Autodesk Fusion 360 part; units mm, degrees
(part 3 of 4)
sketch "SRD relay envelope 1 sketch" plane through (0, 0, 9.6) normal (0, 0, 1) x (1, 0, 0) in component "REF relay envelope 75.5x55x20 - variant not confirmed"
  line L0 (36.75, 131) -> (52.25, 131)
  line L1 (52.25, 131) -> (52.25, 150)
  line L2 (52.25, 150) -> (36.75, 150)
  line L3 (36.75, 150) -> (36.75, 131)
extrude "SRD relay envelope 1" add sketch "SRD relay envelope 1 sketch" along normal blind 15.5 separate body makes body 31 in component "REF relay envelope 75.5x55x20 - variant not confirmed"
ref_plane "WorkPlane3" through (0, 0, 9.6) normal (0, 0, 1) x (1, 0, 0) in component "REF relay envelope 75.5x55x20 - variant not confirmed"
sketch "SRD relay envelope 2 sketch" plane through (0, 0, 9.6) normal (0, 0, 1) x (1, 0, 0) in component "REF relay envelope 75.5x55x20 - variant not confirmed"
  line L0 (54.05, 131) -> (69.55, 131)
  line L1 (69.55, 131) -> (69.55, 150)
  line L2 (69.55, 150) -> (54.05, 150)
  line L3 (54.05, 150) -> (54.05, 131)
extrude "SRD relay envelope 2" add sketch "SRD relay envelope 2 sketch" along normal blind 15.5 separate body makes body 32 in component "REF relay envelope 75.5x55x20 - variant not confirmed"
ref_plane "WorkPlane4" through (0, 0, 9.6) normal (0, 0, 1) x (1, 0, 0) in component "REF relay envelope 75.5x55x20 - variant not confirmed"
sketch "SRD relay envelope 3 sketch" plane through (0, 0, 9.6) normal (0, 0, 1) x (1, 0, 0) in component "REF relay envelope 75.5x55x20 - variant not confirmed"
  line L0 (71.35, 131) -> (86.85, 131)
  line L1 (86.85, 131) -> (86.85, 150)
  line L2 (86.85, 150) -> (71.35, 150)
  line L3 (71.35, 150) -> (71.35, 131)
extrude "SRD relay envelope 3" add sketch "SRD relay envelope 3 sketch" along normal blind 15.5 separate body makes body 33 in component "REF relay envelope 75.5x55x20 - variant not confirmed"
ref_plane "WorkPlane5" through (0, 0, 9.6) normal (0, 0, 1) x (1, 0, 0) in component "REF relay envelope 75.5x55x20 - variant not confirmed"
sketch "SRD relay envelope 4 sketch" plane through (0, 0, 9.6) normal (0, 0, 1) x (1, 0, 0) in component "REF relay envelope 75.5x55x20 - variant not confirmed"
  line L0 (88.65, 131) -> (104.15, 131)
  line L1 (104.15, 131) -> (104.15, 150)
  line L2 (104.15, 150) -> (88.65, 150)
  line L3 (88.65, 150) -> (88.65, 131)
extrude "SRD relay envelope 4" add sketch "SRD relay envelope 4 sketch" along normal blind 15.5 separate body makes body 34 in component "REF relay envelope 75.5x55x20 - variant not confirmed"
ref_plane "WorkPlane6" through (0, 0, 9.6) normal (0, 0, 1) x (1, 0, 0) in component "REF relay envelope 75.5x55x20 - variant not confirmed"
sketch "Terminal strip envelope sketch" plane through (0, 0, 9.6) normal (0, 0, 1) x (1, 0, 0) in component "REF relay envelope 75.5x55x20 - variant not confirmed"
  line L0 (37, 155) -> (103, 155)
  line L1 (103, 155) -> (103, 165)
  line L2 (103, 165) -> (37, 165)
  line L3 (37, 165) -> (37, 155)
extrude "Terminal strip envelope" add sketch "Terminal strip envelope sketch" along normal blind 12 separate body makes body 35 in component "REF relay envelope 75.5x55x20 - variant not confirmed"
ref_plane "WorkPlane7" through (0, 0, 9.6) normal (0, 0, 1) x (1, 0, 0) in component "REF relay envelope 75.5x55x20 - variant not confirmed"
sketch "Control connector reserve sketch" plane through (0, 0, 9.6) normal (0, 0, 1) x (1, 0, 0) in component "REF relay envelope 75.5x55x20 - variant not confirmed"
  line L0 (41, 114) -> (77, 114)
  line L1 (77, 114) -> (77, 119)
  line L2 (77, 119) -> (41, 119)
  line L3 (41, 119) -> (41, 114)
extrude "Control connector reserve" add sketch "Control connector reserve sketch" along normal blind 18.4 separate body makes body 36 in component "REF relay envelope 75.5x55x20 - variant not confirmed"
ref_plane "WorkPlane1" through (0, 0, 49.6) normal (0, 0, 1) x (1, 0, 0) in component "REF LCD2004 98x60 - 93x55 mounting - conservative thickness"
sketch "LCD PCB 98x60 sketch" plane through (0, 0, 49.6) normal (0, 0, 1) x (1, 0, 0) in component "REF LCD2004 98x60 - 93x55 mounting - conservative thickness"
  line L0 (21, 98) -> (119, 98)
  line L1 (119, 98) -> (119, 158)
  line L2 (119, 158) -> (21, 158)
  line L3 (21, 158) -> (21, 98)
extrude "LCD PCB 98x60" add sketch "LCD PCB 98x60 sketch" along normal blind 1.6 separate body makes body 37 in component "REF LCD2004 98x60 - 93x55 mounting - conservative thickness"
ref_plane "WorkPlane2" through (0, 0, 49.5) normal (0, 0, 1) x (1, 0, 0) in component "REF LCD2004 98x60 - 93x55 mounting - conservative thickness"
sketch "LCD minimum published hole diameter sketch" plane through (0, 0, 49.5) normal (0, 0, 1) x (1, 0, 0) in component "REF LCD2004 98x60 - 93x55 mounting - conservative thickness"
  circle A0 centre (23.5, 100.5) radius 1.25
  circle A1 centre (116.5, 100.5) radius 1.25
  circle A2 centre (23.5, 155.5) radius 1.25
  circle A3 centre (116.5, 155.5) radius 1.25
extrude "LCD minimum published hole diameter" cut sketch "LCD minimum published hole diameter sketch" along normal blind 1.8 bodies 37 in component "REF LCD2004 98x60 - 93x55 mounting - conservative thickness"
ref_plane "WorkPlane3" through (0, 0, 51.2) normal (0, 0, 1) x (1, 0, 0) in component "REF LCD2004 98x60 - 93x55 mounting - conservative thickness"
sketch "LCD bezel depth envelope sketch" plane through (0, 0, 51.2) normal (0, 0, 1) x (1, 0, 0) in component "REF LCD2004 98x60 - 93x55 mounting - conservative thickness"
  line L0 (21.5, 108.8) -> (118.5, 108.8)
  line L1 (118.5, 108.8) -> (118.5, 147.2)
  line L2 (118.5, 147.2) -> (21.5, 147.2)
  line L3 (21.5, 147.2) -> (21.5, 108.8)
extrude "LCD bezel depth envelope" add sketch "LCD bezel depth envelope sketch" along normal blind 12 separate body makes body 38 in component "REF LCD2004 98x60 - 93x55 mounting - conservative thickness"
ref_plane "WorkPlane4" through (0, 0, 63.2) normal (0, 0, 1) x (1, 0, 0) in component "REF LCD2004 98x60 - 93x55 mounting - conservative thickness"
sketch "LCD viewing area envelope sketch" plane through (0, 0, 63.2) normal (0, 0, 1) x (1, 0, 0) in component "REF LCD2004 98x60 - 93x55 mounting - conservative thickness"
  line L0 (31.5, 115.4) -> (108.5, 115.4)
  line L1 (108.5, 115.4) -> (108.5, 140.6)
  line L2 (108.5, 140.6) -> (31.5, 140.6)
  line L3 (31.5, 140.6) -> (31.5, 115.4)
extrude "LCD viewing area envelope" add sketch "LCD viewing area envelope sketch" along normal blind 0.1 separate body makes body 39 in component "REF LCD2004 98x60 - 93x55 mounting - conservative thickness"
ref_plane "WorkPlane5" through (0, 0, 39.2) normal (0, 0, 1) x (1, 0, 0) in component "REF LCD2004 98x60 - 93x55 mounting - conservative thickness"
sketch "LCD I2C backpack reserve sketch" plane through (0, 0, 39.2) normal (0, 0, 1) x (1, 0, 0) in component "REF LCD2004 98x60 - 93x55 mounting - conservative thickness"
  line L0 (32, 100) -> (74, 100)
  line L1 (74, 100) -> (74, 118)
  line L2 (74, 118) -> (32, 118)
  line L3 (32, 118) -> (32, 100)
extrude "LCD I2C backpack reserve" add sketch "LCD I2C backpack reserve sketch" along normal blind 10.4 separate body makes body 40 in component "REF LCD2004 98x60 - 93x55 mounting - conservative thickness"
sketch "Sketch1" plane through (0, 0, 0) normal (0, -1, 0) x (1, 0, 0)
  line L0 (6, 0) -> (134, 0)
  line L1 (134, 0) -> (134, 64)
  line L2 (134, 64) -> (6, 64)
  line L3 (6, 64) -> (6, 0)
  line L4 (6, 64) -> (134, 64)
  line L5 (134, 64) -> (134, 0)
  line L6 (134, 0) -> (6, 0)
  line L7 (6, 0) -> (6, 64)
  line L8 (50, 52) -> (90, 52)
  line L9 (90, 52) -> (90, 12)
  line L10 (90, 12) -> (50, 12)
  line L11 (50, 12) -> (50, 52)
  dimension "d962" = 128
  dimension "d963" = 64
  dimension "d964" = 40
  dimension "d965" = 40
  dimension "d966" = 44
  dimension "d967" = 12
  constraint horizontal L4
  constraint vertical L5
  constraint horizontal L6
  constraint vertical L7
  constraint coincident L0.end L1.start
  constraint coincident L2.end L3.start
  constraint horizontal L8
  constraint vertical L9
  constraint horizontal L10
  constraint vertical L11
  measures "d962" distance of L2.end L1.end
  measures "d963" distance of L2.end L0.start
  measures "d964" distance of L8.start L8.end
  measures "d965" distance of L8.start L10.end
  measures "d966" distance of L7 L11
  measures "d967" distance of L4 L8
extrude "Extrude41" cut sketch "Sketch1" against normal blind 3 contours L8 L9 L10 L11 bodies 1 in component "01 BASE - PCB at bottom"
split "Split1" by plane through (70, 45, 32) normal (0, 1, 0) bodies 1 makes body 41 at (46.6667, 131, 0) in component "01 BASE - PCB at bottom"
sketch "Sketch2" plane through (0, 3, 0) normal (0, 1, 0) x (-1, 0, 0)
  line L0 (-90, 12) -> (-90, 52)
  line L1 (-90, 52) -> (-50, 52)
  line L2 (-50, 52) -> (-50, 12)
  line L3 (-50, 12) -> (-90, 12)
  line L4 (-13, 3) -> (-13, 64)
  line L5 (-13, 64) -> (-127, 64)
  line L6 (-127, 64) -> (-127, 3)
  line L7 (-127, 3) -> (-13, 3)
  line L8 (-90, 52) -> (-85, 52)
  line L9 (-85, 52) -> (-85, 48)
  line L10 (-86, 47) -> (-90, 47)
  line L11 (-90, 47) -> (-90, 52)
  line L12 (-50, 52) -> (-55, 52)
  line L13 (-55, 52) -> (-55, 48)
  line L14 (-54, 47) -> (-50, 47)
  line L15 (-50, 47) -> (-50, 52)
  line L16 (-50, 12) -> (-55, 12)
  line L17 (-55, 12) -> (-55, 16)
  line L18 (-54, 17) -> (-50, 17)
  line L19 (-50, 17) -> (-50, 12)
  line L20 (-90, 12) -> (-85, 12)
  line L21 (-85, 12) -> (-85, 16)
  line L22 (-86, 17) -> (-90, 17)
  line L23 (-90, 17) -> (-90, 12)
  line L24 (-86, 47) -> (-95, 47)
  line L25 (-95, 47) -> (-95, 57)
  line L26 (-95, 57) -> (-85, 57)
  line L27 (-85, 57) -> (-85, 48)
  line L28 (-86, 17) -> (-95, 17)
  line L29 (-95, 17) -> (-95, 7)
  line L30 (-95, 7) -> (-85, 7)
  line L31 (-85, 7) -> (-85, 16)
  line L32 (-54, 17) -> (-45, 17)
  line L33 (-45, 17) -> (-45, 7)
  line L34 (-45, 7) -> (-55, 7)
  line L35 (-55, 7) -> (-55, 16)
  line L36 (-54, 47) -> (-45, 47)
  line L37 (-45, 47) -> (-45, 57)
  line L38 (-45, 57) -> (-55, 57)
  line L39 (-55, 57) -> (-55, 48)
  arc A0 (-85, 16) -> (-86, 17) centre (-86, 16) ccw
  arc A1 (-54, 17) -> (-55, 16) centre (-54, 16) ccw
  arc A2 (-55, 48) -> (-54, 47) centre (-54, 48) ccw
  arc A3 (-86, 47) -> (-85, 48) centre (-86, 48) ccw
  circle A4 centre (-87.6464, 49.6464) radius 1
  circle A5 centre (-52.3536, 49.6464) radius 1
  circle A6 centre (-52.3536, 14.3536) radius 1
  circle A7 centre (-87.6464, 14.3536) radius 1
  line L40 (-50, 52) -> (-45, 52)
  line L41 (-90, 52) -> (-95, 52)
  dimension "d972" = 1
  dimension "d973" = 1
  dimension "d974" = 1
  dimension "d975" = 1
  dimension "d976" = 2
  dimension "d977" = 2
  dimension "d978" = 2
  dimension "d979" = 2
  constraint horizontal L8
  constraint vertical L9
  constraint horizontal L10
  constraint vertical L11
  constraint coincident L0.end L1.start
  constraint horizontal L12
  constraint vertical L13
  constraint horizontal L14
  constraint vertical L15
  constraint coincident L1.end L2.start
  constraint horizontal L16
  constraint vertical L17
  constraint horizontal L18
  constraint vertical L19
  constraint coincident L2.end L3.start
  constraint horizontal L20
  constraint vertical L21
  constraint horizontal L22
  constraint vertical L23
  constraint coincident L0.start L3.end
  constraint horizontal L24
  constraint vertical L25
  constraint horizontal L26
  constraint vertical L27
  constraint horizontal L28
  constraint vertical L29
  constraint horizontal L30
  constraint vertical L31
  constraint horizontal L32
  constraint vertical L33
  constraint horizontal L34
  constraint vertical L35
  constraint horizontal L36
  constraint vertical L37
  constraint horizontal L38
  constraint vertical L39
  constraint tangent L28 A0
  constraint tangent L21 A0
  constraint tangent L35 A1
  constraint tangent L32 A1
  constraint tangent L13 A2
  constraint tangent L14 A2
  constraint tangent L9 A3
  constraint tangent L24 A3
  constraint midpoint L37 L40.end
  constraint midpoint L25 L41.end
  measures "d972" radius of A0
  measures "d973" radius of A1
  measures "d974" radius of A2
  measures "d975" radius of A3
  measures "d976" diameter of A4
  measures "d977" diameter of A5
  measures "d978" diameter of A6
  measures "d979" diameter of A7
extrude "Extrude42" add sketch "Sketch2" along normal blind -1.5 and the other way blind 3 contours L0 L3 L20 L21 L22 L23 L28 L31 A0 | L0 L1 L8 L9 L10 L11 L24 L27 A3 | L2 L3 L16 L17 L18 L19 L32 L35 A1 | L1 L2 L12 L13 L14 L15 L36 L39 A2 bodies 1 in component "01 BASE - PCB at bottom"
fillet "Fillet1" radius 16 8 edges at (50, 0.75, 47) (50, 0.75, 17) (85, 0.75, 52) (55, 0.75, 52) (90, 0.75, 17) (85, 0.75, 12) (90, 0.75, 47) (55, 0.75, 12) on bodies 1 in component "01 BASE - PCB at bottom"
combine "Combine1" operation add target body 1 tool bodies 41 in component "01 BASE - PCB at bottom"
ref_plane "WorkPlane2" through (10, 90, 32) normal (-1, 0, 0) x (0, -1, 0)
split "Split2" by plane through (10, 90, 32) normal (-1, 0, 0) bodies 1 makes body 42 at (0, 62, 21.3333) in component "01 BASE - PCB at bottom"
sketch "Sketch3" plane through (10, 0, 0) normal (-1, 0, 0) x (0, -1, 0)
  circle A0 centre (-83, 16) radius 5.5
  dimension "d988" = 11
  measures "d988" diameter of A0
extrude "Extrude43" cut sketch "Sketch3" along normal blind 59 draft 5 bodies 42 in component "01 BASE - PCB at bottom"
sketch "Sketch4" plane through (25, 0, 0) normal (1, 0, 0) x (0, 1, 0)
  line L0 (23, 11) -> (39, 11)
  line L1 (39, 11) -> (39, 23)
  line L2 (39, 23) -> (23, 23)
  line L3 (23, 23) -> (23, 11)
  line L4 (23, 23) -> (35, 23)
  line L5 (35, 23) -> (35, 15)
  line L6 (35, 15) -> (23, 15)
  line L7 (23, 15) -> (23, 23)
  dimension "d991" = 12
  dimension "d992" = 8
  constraint horizontal L4
  constraint vertical L5
  constraint horizontal L6
  constraint vertical L7
  constraint coincident L2.end L3.start
  measures "d991" distance of L2.end L4.end
  measures "d992" distance of L2.end L6.end
extrude "Extrude44" cut sketch "Sketch4" along normal blind -25 and the other way blind 20 contours L2 L3 L4 L5 L6 L7 bodies 42 in component "01 BASE - PCB at bottom"
sketch "Sketch5" plane through (0, 0, 0) normal (-1, 0, 0) x (0, -1, 0)
  line L0 (-35, 15) -> (-35, 23)
  line L1 (-35, 23) -> (-23, 23)
  line L2 (-23, 23) -> (-23, 15)
  line L3 (-23, 15) -> (-35, 15)
  circle A0 centre (-83, 16) radius 6.3749
  line L4 (-174, 0) -> (-6, 0)
  line L5 (-6, 0) -> (-6, 64)
  line L6 (-6, 64) -> (-174, 64)
  line L7 (-174, 64) -> (-174, 0)
  circle A1 centre (-41, 19) radius 2
  dimension "d997" = 4
  measures "d997" diameter of A1
extrude "Extrude45" cut sketch "Sketch5" against normal blind 8 contours A1 bodies 42 in component "01 BASE - PCB at bottom"
combine "Combine2" operation add target body 42 tool bodies 1 in component "01 BASE - PCB at bottom"
sketch "Sketch6" plane through (0, 0, 67) normal (0, 0, 1) x (-1, 0, 0)
  spline S0 degree 3 poles (-38.9727, -80.2046) (-38.8334, -80.304) (-38.5543, -80.503) (-38.384, -80.8005) (-38.2988, -80.9495) knots 0 0 0 0 0.050683 0.101518 0.101518 0.101518 0.101518
  spline S1 degree 3 poles (-38.2988, -80.9495) (-38.2319, -81.1092) (-38.0981, -81.4289) (-38.0791, -81.775) (-38.0696, -81.9482) knots 0 0 0 0 0.05152 0.103135 0.103135 0.103135 0.103135
  spline S2 degree 3 poles (-38.0696, -81.9482) (-38.085, -82.2545) (-38.114, -82.8278) (-38.4486, -83.2916) (-38.6044, -83.5075) knots 0 0 0 0 0.08978 0.168002 0.168002 0.168002 0.168002
  spline S3 degree 3 poles (-38.6044, -83.5075) (-38.7988, -83.6718) (-39.1974, -84.0085) (-39.7183, -84.0498) (-39.985, -84.0709) knots 0 0 0 0 0.074417 0.152506 0.152506 0.152506 0.152506
  spline S4 degree 3 poles (-39.985, -84.0709) (-40.1637, -84.0607) (-40.5148, -84.0407) (-40.8292, -83.8835) (-40.9836, -83.8063) knots 0 0 0 0 0.053075 0.104281 0.104281 0.104281 0.104281
  spline S5 degree 3 poles (-40.9836, -83.8063) (-41.1233, -83.7089) (-41.404, -83.5133) (-41.5755, -83.2171) (-41.6617, -83.0682) knots 0 0 0 0 0.050395 0.101317 0.101317 0.101317 0.101317
  spline S6 degree 3 poles (-41.6617, -83.0682) (-41.7297, -82.902) (-41.8704, -82.558) (-41.8866, -82.1865) (-41.895, -81.9945) knots 0 0 0 0 0.053456 0.11061 0.11061 0.11061 0.11061
  spline S7 degree 3 poles (-41.895, -81.9945) (-41.8861, -81.7998) (-41.8688, -81.422) (-41.721, -81.0743) (-41.6494, -80.9059) knots 0 0 0 0 0.057966 0.112404 0.112404 0.112404 0.112404
  spline S8 degree 3 poles (-41.6494, -80.9059) (-41.56, -80.7561) (-41.3836, -80.4604) (-41.0957, -80.2718) (-40.9536, -80.1787) knots 0 0 0 0 0.051579 0.10182 0.10182 0.10182 0.10182
  spline S9 degree 3 poles (-40.9536, -80.1787) (-40.8003, -80.1067) (-40.4923, -79.9621) (-40.1527, -79.9419) (-39.9823, -79.9318) knots 0 0 0 0 0.050326 0.101044 0.101044 0.101044 0.101044
  spline S10 degree 3 poles (-39.9823, -79.9318) (-39.8006, -79.9422) (-39.4448, -79.9625) (-39.1279, -80.1251) (-38.9727, -80.2046) knots 0 0 0 0 0.053912 0.105611 0.105611 0.105611 0.105611
  line L0 (-50.8472, -80.472) -> (-50.8472, -80)
  line L1 (-50.8472, -80) -> (-47.8622, -80)
  line L2 (-47.8622, -80) -> (-47.8622, -84)
  line L3 (-47.8622, -84) -> (-50.7544, -84)
  line L4 (-50.7544, -84) -> (-50.7544, -83.528)
  line L5 (-50.7544, -83.528) -> (-48.3915, -83.528)
  line L6 (-48.3915, -83.528) -> (-48.3915, -82.3029)
  line L7 (-48.3915, -82.3029) -> (-50.6044, -82.3029)
  line L8 (-50.6044, -82.3029) -> (-50.6044, -81.8336)
  line L9 (-50.6044, -81.8336) -> (-48.3915, -81.8336)
  line L10 (-48.3915, -81.8336) -> (-48.3915, -80.472)
  line L11 (-48.3915, -80.472) -> (-50.8472, -80.472)
  line L12 (-59.8404, -84.0682) -> (-58.6835, -79.9318)
  line L13 (-58.6835, -79.9318) -> (-58.2879, -79.9318)
  line L14 (-58.2879, -79.9318) -> (-59.4475, -84.0682)
  line L15 (-59.4475, -84.0682) -> (-59.8404, -84.0682)
  spline S11 degree 3 poles (-67.2265, -80.2046) (-67.0871, -80.304) (-66.8081, -80.503) (-66.6378, -80.8005) (-66.5525, -80.9495) knots 0 0 0 0 0.050683 0.101518 0.101518 0.101518 0.101518
  spline S12 degree 3 poles (-66.5525, -80.9495) (-66.4857, -81.1092) (-66.3519, -81.4289) (-66.3328, -81.775) (-66.3233, -81.9482) knots 0 0 0 0 0.05152 0.103135 0.103135 0.103135 0.103135
  spline S13 degree 3 poles (-66.3233, -81.9482) (-66.3388, -82.2545) (-66.3678, -82.8278) (-66.7023, -83.2916) (-66.8581, -83.5075) knots 0 0 0 0 0.08978 0.168002 0.168002 0.168002 0.168002
  spline S14 degree 3 poles (-66.8581, -83.5075) (-67.0526, -83.6718) (-67.4511, -84.0085) (-67.972, -84.0498) (-68.2387, -84.0709) knots 0 0 0 0 0.074417 0.152506 0.152506 0.152506 0.152506
  spline S15 degree 3 poles (-68.2387, -84.0709) (-68.4175, -84.0607) (-68.7686, -84.0407) (-69.083, -83.8835) (-69.2374, -83.8063) knots 0 0 0 0 0.053074 0.104281 0.104281 0.104281 0.104281
  spline S16 degree 3 poles (-69.2374, -83.8063) (-69.377, -83.7089) (-69.6578, -83.5133) (-69.8292, -83.2171) (-69.9154, -83.0682) knots 0 0 0 0 0.050395 0.101317 0.101317 0.101317 0.101317
  spline S17 degree 3 poles (-69.9154, -83.0682) (-69.9834, -82.902) (-70.1242, -82.558) (-70.1404, -82.1865) (-70.1487, -81.9945) knots 0 0 0 0 0.053456 0.11061 0.11061 0.11061 0.11061
  spline S18 degree 3 poles (-70.1487, -81.9945) (-70.1398, -81.7998) (-70.1226, -81.422) (-69.9747, -81.0743) (-69.9031, -80.9059) knots 0 0 0 0 0.057966 0.112404 0.112404 0.112404 0.112404
  spline S19 degree 3 poles (-69.9031, -80.9059) (-69.8138, -80.7561) (-69.6373, -80.4604) (-69.3494, -80.2718) (-69.2074, -80.1787) knots 0 0 0 0 0.051579 0.10182 0.10182 0.10182 0.10182
  spline S20 degree 3 poles (-69.2074, -80.1787) (-69.054, -80.1067) (-68.7461, -79.9621) (-68.4065, -79.9419) (-68.236, -79.9318) knots 0 0 0 0 0.050325 0.101044 0.101044 0.101044 0.101044
  spline S21 degree 3 poles (-68.236, -79.9318) (-68.0544, -79.9422) (-67.6986, -79.9625) (-67.3816, -80.1251) (-67.2265, -80.2046) knots 0 0 0 0 0.053912 0.105611 0.105611 0.105611 0.105611
  spline S22 degree 3 poles (-72.5143, -80.3847) (-72.6553, -80.3941) (-72.9296, -80.4125) (-73.1569, -80.5664) (-73.2674, -80.6412) knots 0 0 0 0 0.041562 0.080838 0.080838 0.080838 0.080838
  spline S23 degree 3 poles (-73.2674, -80.6412) (-73.3629, -80.7421) (-73.5678, -80.9588) (-73.6441, -81.248) (-73.6849, -81.4025) knots 0 0 0 0 0.041026 0.088063 0.088063 0.088063 0.088063
  line L16 (-73.6849, -81.4025) -> (-74.2142, -81.2688)
  spline S24 degree 3 poles (-74.2142, -81.2688) (-74.1519, -81.0678) (-74.0336, -80.6863) (-73.7496, -80.4066) (-73.6153, -80.2742) knots 0 0 0 0 0.062011 0.117707 0.117707 0.117707 0.117707
  spline S25 degree 3 poles (-73.6153, -80.2742) (-73.4598, -80.1744) (-73.1379, -79.9677) (-72.7556, -79.944) (-72.558, -79.9318) knots 0 0 0 0 0.054488 0.112794 0.112794 0.112794 0.112794
  spline S26 degree 3 poles (-72.558, -79.9318) (-72.3587, -79.939) (-71.9885, -79.9523) (-71.6585, -80.1184) (-71.5061, -80.1951) knots 0 0 0 0 0.058997 0.109567 0.109567 0.109567 0.109567
  spline S27 degree 3 poles (-71.5061, -80.1951) (-71.3781, -80.2951) (-71.114, -80.5015) (-70.9659, -80.8026) (-70.8895, -80.9577) knots 0 0 0 0 0.048078 0.099208 0.099208 0.099208 0.099208
  spline S28 degree 3 poles (-70.8895, -80.9577) (-70.8278, -81.1285) (-70.7027, -81.4751) (-70.6863, -81.8433) (-70.678, -82.03) knots 0 0 0 0 0.054148 0.109856 0.109856 0.109856 0.109856
  spline S29 degree 3 poles (-70.678, -82.03) (-70.686, -82.2277) (-70.7012, -82.6055) (-70.8472, -82.9539) (-70.9168, -83.1201) knots 0 0 0 0 0.058796 0.112388 0.112388 0.112388 0.112388
  spline S30 degree 3 poles (-70.9168, -83.1201) (-71.004, -83.2654) (-71.1765, -83.5529) (-71.4573, -83.7361) (-71.5962, -83.8267) knots 0 0 0 0 0.050116 0.099176 0.099176 0.099176 0.099176
  spline S31 degree 3 poles (-71.5962, -83.8267) (-71.7479, -83.8972) (-72.0556, -84.04) (-72.3945, -84.0587) (-72.5662, -84.0682) knots 0 0 0 0 0.0497 0.100774 0.100774 0.100774 0.100774
  spline S32 degree 3 poles (-72.5662, -84.0682) (-72.755, -84.0578) (-73.117, -84.038) (-73.4273, -83.8517) (-73.5757, -83.7626) knots 0 0 0 0 0.055778 0.106905 0.106905 0.106905 0.106905
  spline S33 degree 3 poles (-73.5757, -83.7626) (-73.7026, -83.6475) (-73.965, -83.4096) (-74.0843, -83.0756) (-74.146, -82.9031) knots 0 0 0 0 0.05057 0.104573 0.104573 0.104573 0.104573
  line L17 (-74.146, -82.9031) -> (-73.6248, -82.7804)
  spline S34 degree 3 poles (-73.6248, -82.7804) (-73.5777, -82.9124) (-73.4908, -83.1556) (-73.3056, -83.3344) (-73.221, -83.4161) knots 0 0 0 0 0.041397 0.07622 0.07622 0.07622 0.07622
  spline S35 degree 3 poles (-73.221, -83.4161) (-73.124, -83.4742) (-72.9193, -83.5966) (-72.6807, -83.6088) (-72.5552, -83.6153) knots 0 0 0 0 0.033404 0.070439 0.070439 0.070439 0.070439
  spline S36 degree 3 poles (-72.5552, -83.6153) (-72.4108, -83.6081) (-72.1362, -83.5945) (-71.8976, -83.4587) (-71.7844, -83.3943) knots 0 0 0 0 0.042685 0.08119 0.08119 0.08119 0.08119
  spline S37 degree 3 poles (-71.7844, -83.3943) (-71.6887, -83.3138) (-71.4956, -83.1513) (-71.3983, -82.9183) (-71.3493, -82.8008) knots 0 0 0 0 0.036949 0.074549 0.074549 0.074549 0.074549
  spline S38 degree 3 poles (-71.3493, -82.8008) (-71.3126, -82.6756) (-71.2393, -82.4247) (-71.2289, -82.1635) (-71.2237, -82.0327) knots 0 0 0 0 0.038978 0.078088 0.078088 0.078088 0.078088
  spline S39 degree 3 poles (-71.2237, -82.0327) (-71.2284, -81.8721) (-71.2372, -81.5682) (-71.3291, -81.2785) (-71.3724, -81.1419) knots 0 0 0 0 0.047928 0.09071 0.09071 0.09071 0.09071
  spline S40 degree 3 poles (-71.3724, -81.1419) (-71.4272, -81.024) (-71.5337, -80.7952) (-71.7365, -80.6456) (-71.8349, -80.573) knots 0 0 0 0 0.038298 0.074371 0.074371 0.074371 0.074371
  spline S41 degree 3 poles (-71.8349, -80.573) (-71.9417, -80.5181) (-72.1551, -80.4083) (-72.3946, -80.3926) (-72.5143, -80.3847) knots 0 0 0 0 0.035595 0.071173 0.071173 0.071173 0.071173
  line L18 (-82.8199, -84.0682) -> (-81.663, -79.9318)
  line L19 (-81.663, -79.9318) -> (-81.2674, -79.9318)
  line L20 (-81.2674, -79.9318) -> (-82.427, -84.0682)
  line L21 (-82.427, -84.0682) -> (-82.8199, -84.0682)
  spline S42 degree 3 poles (-92.4598, -80.6739) (-92.5315, -80.8001) (-92.7093, -81.1127) (-92.7085, -81.4754) (-92.708, -81.6917) knots 0 0 0 0 0.042926 0.106327 0.106327 0.106327 0.106327
  line L22 (-92.708, -81.6917) -> (-92.708, -84)
  line L23 (-92.708, -84) -> (-93.2374, -84)
  line L24 (-93.2374, -84) -> (-93.2374, -81.6889)
  spline S43 degree 3 poles (-93.2374, -81.6889) (-93.2349, -81.5073) (-93.2304, -81.1818) (-93.1406, -80.8693) (-93.101, -80.7312) knots 0 0 0 0 0.0542 0.097116 0.097116 0.097116 0.097116
  spline S44 degree 3 poles (-93.101, -80.7312) (-93.0448, -80.6176) (-92.9294, -80.384) (-92.7173, -80.2321) (-92.6085, -80.1542) knots 0 0 0 0 0.037423 0.076915 0.076915 0.076915 0.076915
  spline S45 degree 3 poles (-92.6085, -80.1542) (-92.4735, -80.0894) (-92.1789, -79.948) (-91.8514, -79.9375) (-91.6739, -79.9318) knots 0 0 0 0 0.044416 0.096996 0.096996 0.096996 0.096996
  spline S46 degree 3 poles (-91.6739, -79.9318) (-91.5012, -79.9368) (-91.1824, -79.946) (-90.8889, -80.0691) (-90.7544, -80.1255) knots 0 0 0 0 0.05132 0.094686 0.094686 0.094686 0.094686
  spline S47 degree 3 poles (-90.7544, -80.1255) (-90.644, -80.1969) (-90.4244, -80.3389) (-90.304, -80.5709) (-90.2442, -80.6862) knots 0 0 0 0 0.038729 0.076986 0.076986 0.076986 0.076986
  spline S48 degree 3 poles (-90.2442, -80.6862) (-90.1998, -80.8299) (-90.099, -81.156) (-90.0941, -81.4978) (-90.0914, -81.6889) knots 0 0 0 0 0.044904 0.101888 0.101888 0.101888 0.101888
  line L25 (-90.0914, -81.6889) -> (-90.0914, -84)
  line L26 (-90.0914, -84) -> (-90.6207, -84)
  line L27 (-90.6207, -84) -> (-90.6207, -81.6917)
  spline S49 degree 3 poles (-90.6207, -81.6917) (-90.6213, -81.5398) (-90.6222, -81.2793) (-90.6895, -81.0282) (-90.7176, -80.9236) knots 0 0 0 0 0.045324 0.077698 0.077698 0.077698 0.077698
  spline S50 degree 3 poles (-90.7176, -80.9236) (-90.7559, -80.8459) (-90.833, -80.6895) (-90.9777, -80.592) (-91.0505, -80.543) knots 0 0 0 0 0.02552 0.051354 0.051354 0.051354 0.051354
  spline S51 degree 3 poles (-91.0505, -80.543) (-91.1366, -80.504) (-91.3197, -80.4211) (-91.5209, -80.4134) (-91.6276, -80.4093) knots 0 0 0 0 0.028079 0.059737 0.059737 0.059737 0.059737
  spline S52 degree 3 poles (-91.6276, -80.4093) (-91.8005, -80.4132) (-92.1063, -80.4201) (-92.3527, -80.5971) (-92.4598, -80.6739) knots 0 0 0 0 0.050435 0.089134 0.089134 0.089134 0.089134
  line L28 (-101.2019, -80.824) -> (-101.2019, -81.5689)
  line L29 (-101.2019, -81.5689) -> (-100.0259, -81.5689)
  line L30 (-100.0259, -81.5689) -> (-100.0259, -82.0382)
  line L31 (-100.0259, -82.0382) -> (-101.7203, -82.0409)
  line L32 (-101.7203, -82.0409) -> (-101.7203, -80.5566)
  spline S53 degree 3 poles (-101.7203, -80.5566) (-101.5914, -80.4602) (-101.3412, -80.273) (-101.0545, -80.1489) (-100.9154, -80.0887) knots 0 0 0 0 0.048097 0.093389 0.093389 0.093389 0.093389
  spline S54 degree 3 poles (-100.9154, -80.0887) (-100.7766, -80.0429) (-100.4999, -79.9518) (-100.209, -79.9384) (-100.0641, -79.9318) knots 0 0 0 0 0.043635 0.086924 0.086924 0.086924 0.086924
  spline S55 degree 3 poles (-100.0641, -79.9318) (-99.8739, -79.9414) (-99.5014, -79.9602) (-99.1602, -80.1106) (-98.9932, -80.1842) knots 0 0 0 0 0.056595 0.110855 0.110855 0.110855 0.110855
  spline S56 degree 3 poles (-98.9932, -80.1842) (-98.8426, -80.2774) (-98.5425, -80.4633) (-98.358, -80.7641) (-98.266, -80.9141) knots 0 0 0 0 0.052331 0.10431 0.10431 0.10431 0.10431
  spline S57 degree 3 poles (-98.266, -80.9141) (-98.1944, -81.0802) (-98.0476, -81.4206) (-98.0297, -81.7911) (-98.0205, -81.9809) knots 0 0 0 0 0.053797 0.11027 0.11027 0.11027 0.11027
  spline S58 degree 3 poles (-98.0205, -81.9809) (-98.0302, -82.1714) (-98.0496, -82.5488) (-98.1934, -82.898) (-98.2647, -83.0709) knots 0 0 0 0 0.056775 0.112433 0.112433 0.112433 0.112433
  spline S59 degree 3 poles (-98.2647, -83.0709) (-98.3533, -83.2279) (-98.527, -83.5354) (-98.8226, -83.7282) (-98.9673, -83.8226) knots 0 0 0 0 0.05321 0.104243 0.104243 0.104243 0.104243
  spline S60 degree 3 poles (-98.9673, -83.8226) (-99.1292, -83.8942) (-99.4654, -84.0428) (-99.8328, -84.0595) (-100.0232, -84.0682) knots 0 0 0 0 0.052644 0.109254 0.109254 0.109254 0.109254
  spline S61 degree 3 poles (-100.0232, -84.0682) (-100.1621, -84.0632) (-100.4304, -84.0536) (-100.6849, -83.9687) (-100.8076, -83.9277) knots 0 0 0 0 0.041452 0.08006 0.08006 0.08006 0.08006
  spline S62 degree 3 poles (-100.8076, -83.9277) (-100.9166, -83.8782) (-101.1255, -83.7833) (-101.2824, -83.6161) (-101.3574, -83.5362) knots 0 0 0 0 0.035508 0.068081 0.068081 0.068081 0.068081
  spline S63 degree 3 poles (-101.3574, -83.5362) (-101.4208, -83.4421) (-101.5568, -83.2403) (-101.6243, -83.0062) (-101.6603, -82.8813) knots 0 0 0 0 0.03382 0.072544 0.072544 0.072544 0.072544
  line L33 (-101.6603, -82.8813) -> (-101.1828, -82.7503)
  spline S64 degree 3 poles (-101.1828, -82.7503) (-101.1535, -82.8433) (-101.0998, -83.0134) (-101.003, -83.1628) (-100.9591, -83.2306) knots 0 0 0 0 0.029093 0.053192 0.053192 0.053192 0.053192
  spline S65 degree 3 poles (-100.9591, -83.2306) (-100.9077, -83.2867) (-100.7992, -83.4053) (-100.6537, -83.474) (-100.5771, -83.5102) knots 0 0 0 0 0.0226 0.047747 0.047747 0.047747 0.047747
  spline S66 degree 3 poles (-100.5771, -83.5102) (-100.4906, -83.5409) (-100.3123, -83.604) (-100.1233, -83.6115) (-100.0259, -83.6153) knots 0 0 0 0 0.027353 0.056394 0.056394 0.056394 0.056394
  spline S67 degree 3 poles (-100.0259, -83.6153) (-99.9121, -83.6119) (-99.6973, -83.6055) (-99.4939, -83.537) (-99.3984, -83.5048) knots 0 0 0 0 0.033946 0.064033 0.064033 0.064033 0.064033
  spline S68 degree 3 poles (-99.3984, -83.5048) (-99.3157, -83.4665) (-99.1573, -83.393) (-99.0315, -83.272) (-98.9714, -83.2142) knots 0 0 0 0 0.027115 0.051971 0.051971 0.051971 0.051971
  spline S69 degree 3 poles (-98.9714, -83.2142) (-98.9204, -83.153) (-98.8194, -83.0319) (-98.7522, -82.8892) (-98.719, -82.8186) knots 0 0 0 0 0.023773 0.047099 0.047099 0.047099 0.047099
  spline S70 degree 3 poles (-98.719, -82.8186) (-98.6744, -82.6909) (-98.5835, -82.4302) (-98.572, -82.1543) (-98.5662, -82.0136) knots 0 0 0 0 0.040339 0.082327 0.082327 0.082327 0.082327
  spline S71 degree 3 poles (-98.5662, -82.0136) (-98.5714, -81.8478) (-98.5811, -81.5383) (-98.6967, -81.2517) (-98.7503, -81.1187) knots 0 0 0 0 0.049329 0.092008 0.092008 0.092008 0.092008
  spline S72 degree 3 poles (-98.7503, -81.1187) (-98.8183, -81.0066) (-98.953, -80.7842) (-99.1759, -80.6503) (-99.2865, -80.5839) knots 0 0 0 0 0.038677 0.076751 0.076751 0.076751 0.076751
  spline S73 degree 3 poles (-99.2865, -80.5839) (-99.4058, -80.533) (-99.6447, -80.4309) (-99.9042, -80.4165) (-100.0341, -80.4093) knots 0 0 0 0 0.03858 0.077299 0.077299 0.077299 0.077299
  spline S74 degree 3 poles (-100.0341, -80.4093) (-100.1484, -80.4149) (-100.3786, -80.4263) (-100.5959, -80.503) (-100.7053, -80.5416) knots 0 0 0 0 0.034131 0.068736 0.068736 0.068736 0.068736
  spline S75 degree 3 poles (-100.7053, -80.5416) (-100.8037, -80.583) (-100.9807, -80.6574) (-101.1339, -80.7728) (-101.2019, -80.824) knots 0 0 0 0 0.03187 0.057321 0.057321 0.057321 0.057321
  line L34 (-94.6562, -81.7763) -> (-94.6562, -80)
  line L35 (-94.6562, -80) -> (-94.1269, -80)
  line L36 (-94.1269, -80) -> (-94.1269, -84)
  line L37 (-94.1269, -84) -> (-95.9004, -84)
  spline S76 degree 3 poles (-95.9004, -84) (-96.0584, -83.9988) (-96.3344, -83.9967) (-96.6, -83.9235) (-96.7135, -83.8922) knots 0 0 0 0 0.047145 0.082328 0.082328 0.082328 0.082328
  spline S77 degree 3 poles (-96.7135, -83.8922) (-96.8021, -83.8486) (-96.9827, -83.7597) (-97.099, -83.5953) (-97.1583, -83.5116) knots 0 0 0 0 0.029134 0.059371 0.059371 0.059371 0.059371
  spline S78 degree 3 poles (-97.1583, -83.5116) (-97.2068, -83.4178) (-97.3047, -83.2286) (-97.318, -83.0159) (-97.3247, -82.9086) knots 0 0 0 0 0.031313 0.063169 0.063169 0.063169 0.063169
  spline S79 degree 3 poles (-97.3247, -82.9086) (-97.314, -82.7731) (-97.2929, -82.5065) (-97.1295, -82.295) (-97.0491, -82.191) knots 0 0 0 0 0.039823 0.07837 0.07837 0.07837 0.07837
  spline S80 degree 3 poles (-97.0491, -82.191) (-96.9367, -82.1016) (-96.6871, -81.9032) (-96.3714, -81.8494) (-96.1978, -81.8199) knots 0 0 0 0 0.042418 0.094206 0.094206 0.094206 0.094206
  spline S81 degree 3 poles (-96.1978, -81.8199) (-96.2609, -81.7888) (-96.374, -81.7329) (-96.4732, -81.6551) (-96.5171, -81.6207) knots 0 0 0 0 0.02103 0.037715 0.037715 0.037715 0.037715
  spline S82 degree 3 poles (-96.5171, -81.6207) (-96.5948, -81.543) (-96.7582, -81.3798) (-96.8882, -81.1888) (-96.9563, -81.0887) knots 0 0 0 0 0.032909 0.069134 0.069134 0.069134 0.069134
  line L38 (-96.9563, -81.0887) -> (-97.6521, -80)
  line L39 (-97.6521, -80) -> (-96.9864, -80)
  line L40 (-96.9864, -80) -> (-96.457, -80.8322)
  spline S83 degree 3 poles (-96.457, -80.8322) (-96.3879, -80.9391) (-96.2663, -81.1268) (-96.1326, -81.3061) (-96.075, -81.3834) knots 0 0 0 0 0.038178 0.067075 0.067075 0.067075 0.067075
  spline S84 degree 3 poles (-96.075, -81.3834) (-96.0299, -81.4398) (-95.9503, -81.5392) (-95.8498, -81.6171) (-95.8063, -81.6508) knots 0 0 0 0 0.021583 0.038029 0.038029 0.038029 0.038029
  spline S85 degree 3 poles (-95.8063, -81.6508) (-95.7672, -81.6741) (-95.691, -81.7196) (-95.6061, -81.7449) (-95.5648, -81.7572) knots 0 0 0 0 0.013613 0.026481 0.026481 0.026481 0.026481
  spline S86 degree 3 poles (-95.5648, -81.7572) (-95.5253, -81.7627) (-95.4276, -81.7763) (-95.3289, -81.7763) (-95.2701, -81.7763) knots 0 0 0 0 0.011955 0.02956 0.02956 0.02956 0.02956
  line L41 (-95.2701, -81.7763) -> (-94.6562, -81.7763)
  line L42 (-86.8854, -81.6262) -> (-86.8854, -80)
  line L43 (-86.8854, -80) -> (-86.3561, -80)
  line L44 (-86.3561, -80) -> (-86.3561, -84)
  line L45 (-86.3561, -84) -> (-87.8649, -84)
  spline S87 degree 3 poles (-87.8649, -84) (-87.9822, -83.9996) (-88.1859, -83.999) (-88.3878, -83.9729) (-88.4734, -83.9618) knots 0 0 0 0 0.035143 0.061017 0.061017 0.061017 0.061017
  spline S88 degree 3 poles (-88.4734, -83.9618) (-88.5656, -83.9431) (-88.7406, -83.9076) (-88.8945, -83.8175) (-88.9673, -83.7749) knots 0 0 0 0 0.028003 0.053128 0.053128 0.053128 0.053128
  spline S89 degree 3 poles (-88.9673, -83.7749) (-89.0311, -83.723) (-89.1632, -83.6155) (-89.2454, -83.4661) (-89.2879, -83.3888) knots 0 0 0 0 0.024427 0.050606 0.050606 0.050606 0.050606
  spline S90 degree 3 poles (-89.2879, -83.3888) (-89.3233, -83.3031) (-89.3955, -83.1283) (-89.4046, -82.9394) (-89.4093, -82.8431) knots 0 0 0 0 0.027603 0.056277 0.056277 0.056277 0.056277
  spline S91 degree 3 poles (-89.4093, -82.8431) (-89.3967, -82.6806) (-89.3719, -82.361) (-89.1793, -82.1053) (-89.0846, -81.9795) knots 0 0 0 0 0.047795 0.093992 0.093992 0.093992 0.093992
  spline S92 degree 3 poles (-89.0846, -81.9795) (-88.9374, -81.8771) (-88.5885, -81.6342) (-88.1594, -81.6291) (-87.9113, -81.6262) knots 0 0 0 0 0.052712 0.125013 0.125013 0.125013 0.125013
  line L46 (-87.9113, -81.6262) -> (-86.8854, -81.6262)
  line L47 (-75.3738, -81.3861) -> (-75.3738, -80)
  line L48 (-75.3738, -80) -> (-74.8445, -80)
  line L49 (-74.8445, -80) -> (-74.8445, -84)
  line L50 (-74.8445, -84) -> (-75.3738, -84)
  line L51 (-75.3738, -84) -> (-75.3738, -82.0164)
  line L52 (-75.3738, -82.0164) -> (-77.3602, -84)
  line L53 (-77.3602, -84) -> (-78.0778, -84)
  line L54 (-78.0778, -84) -> (-76.3997, -82.3793)
  line L55 (-76.3997, -82.3793) -> (-78.1514, -80)
  line L56 (-78.1514, -80) -> (-77.4529, -80)
  line L57 (-77.4529, -80) -> (-76.0286, -82.0246)
  line L58 (-76.0286, -82.0246) -> (-75.3738, -81.3861)
  line L59 (-105.4966, -80.472) -> (-105.4966, -80)
  line L60 (-105.4966, -80) -> (-102.5116, -80)
  line L61 (-102.5116, -80) -> (-102.5116, -84)
  line L62 (-102.5116, -84) -> (-105.4038, -84)
  line L63 (-105.4038, -84) -> (-105.4038, -83.528)
  line L64 (-105.4038, -83.528) -> (-103.0409, -83.528)
  line L65 (-103.0409, -83.528) -> (-103.0409, -82.3029)
  line L66 (-103.0409, -82.3029) -> (-105.2537, -82.3029)
  line L67 (-105.2537, -82.3029) -> (-105.2537, -81.8336)
  line L68 (-105.2537, -81.8336) -> (-103.0409, -81.8336)
  line L69 (-103.0409, -81.8336) -> (-103.0409, -80.472)
  line L70 (-103.0409, -80.472) -> (-105.4966, -80.472)
  line L71 (-65.854, -80.472) -> (-65.854, -80)
  line L72 (-65.854, -80) -> (-63.3547, -80)
  line L73 (-63.3547, -80) -> (-63.3547, -84)
  line L74 (-63.3547, -84) -> (-63.884, -84)
  line L75 (-63.884, -84) -> (-63.884, -80.472)
  line L76 (-63.884, -80.472) -> (-65.854, -80.472)
  line L77 (-52.116, -81.7763) -> (-52.116, -80)
  line L78 (-52.116, -80) -> (-51.5866, -80)
  line L79 (-51.5866, -80) -> (-51.5866, -84)
  line L80 (-51.5866, -84) -> (-53.3602, -84)
  spline S93 degree 3 poles (-53.3602, -84) (-53.5182, -83.9988) (-53.7941, -83.9967) (-54.0598, -83.9235) (-54.1733, -83.8922) knots 0 0 0 0 0.047144 0.082328 0.082328 0.082328 0.082328
  spline S94 degree 3 poles (-54.1733, -83.8922) (-54.2619, -83.8486) (-54.4424, -83.7597) (-54.5588, -83.5953) (-54.618, -83.5116) knots 0 0 0 0 0.029135 0.059371 0.059371 0.059371 0.059371
  spline S95 degree 3 poles (-54.618, -83.5116) (-54.6666, -83.4178) (-54.7645, -83.2286) (-54.7778, -83.0159) (-54.7844, -82.9086) knots 0 0 0 0 0.031313 0.063169 0.063169 0.063169 0.063169
  spline S96 degree 3 poles (-54.7844, -82.9086) (-54.7737, -82.7731) (-54.7526, -82.5065) (-54.5892, -82.295) (-54.5089, -82.191) knots 0 0 0 0 0.039823 0.07837 0.07837 0.07837 0.07837
  spline S97 degree 3 poles (-54.5089, -82.191) (-54.3965, -82.1016) (-54.1468, -81.9032) (-53.8311, -81.8494) (-53.6576, -81.8199) knots 0 0 0 0 0.042418 0.094206 0.094206 0.094206 0.094206
  spline S98 degree 3 poles (-53.6576, -81.8199) (-53.7206, -81.7888) (-53.8337, -81.7329) (-53.9329, -81.6551) (-53.9768, -81.6207) knots 0 0 0 0 0.02103 0.037715 0.037715 0.037715 0.037715
  spline S99 degree 3 poles (-53.9768, -81.6207) (-54.0546, -81.543) (-54.218, -81.3798) (-54.348, -81.1888) (-54.4161, -81.0887) knots 0 0 0 0 0.032909 0.069134 0.069134 0.069134 0.069134
  line L81 (-54.4161, -81.0887) -> (-55.1119, -80)
  line L82 (-55.1119, -80) -> (-54.4461, -80)
  line L83 (-54.4461, -80) -> (-53.9168, -80.8322)
  spline S100 degree 3 poles (-53.9168, -80.8322) (-53.8476, -80.9391) (-53.7261, -81.1268) (-53.5924, -81.3061) (-53.5348, -81.3834) knots 0 0 0 0 0.038178 0.067075 0.067075 0.067075 0.067075
  spline S101 degree 3 poles (-53.5348, -81.3834) (-53.4896, -81.4398) (-53.4101, -81.5392) (-53.3095, -81.6171) (-53.266, -81.6508) knots 0 0 0 0 0.021583 0.038029 0.038029 0.038029 0.038029
  spline S102 degree 3 poles (-53.266, -81.6508) (-53.2269, -81.6741) (-53.1508, -81.7196) (-53.0658, -81.7449) (-53.0246, -81.7572) knots 0 0 0 0 0.013613 0.02648 0.02648 0.02648 0.02648
  spline S103 degree 3 poles (-53.0246, -81.7572) (-52.985, -81.7627) (-52.8874, -81.7763) (-52.7887, -81.7763) (-52.7299, -81.7763) knots 0 0 0 0 0.011955 0.029561 0.029561 0.029561 0.029561
  line L84 (-52.7299, -81.7763) -> (-52.116, -81.7763)
  line L85 (-44.6644, -83.0477) -> (-43.8158, -80)
  line L86 (-43.8158, -80) -> (-43.2756, -80)
  line L87 (-43.2756, -80) -> (-42.2142, -84)
  line L88 (-42.2142, -84) -> (-42.7572, -84)
  line L89 (-42.7572, -84) -> (-43.3656, -81.3779)
  spline S104 degree 3 poles (-43.3656, -81.3779) (-43.3971, -81.2412) (-43.4598, -80.9697) (-43.5099, -80.6955) (-43.5348, -80.5593) knots 0 0 0 0 0.042069 0.083595 0.083595 0.083595 0.083595
  spline S105 degree 3 poles (-43.5348, -80.5593) (-43.5747, -80.728) (-43.6331, -80.9748) (-43.6952, -81.2208) (-43.7149, -81.2988) knots 0 0 0 0 0.051984 0.076105 0.076105 0.076105 0.076105
  line L90 (-43.7149, -81.2988) -> (-44.4761, -84)
  line L91 (-44.4761, -84) -> (-45.1146, -84)
  line L92 (-45.1146, -84) -> (-45.6876, -81.9754)
  spline S106 degree 3 poles (-45.6876, -81.9754) (-45.7537, -81.7329) (-45.8811, -81.266) (-45.9605, -80.7887) (-45.9986, -80.5593) knots 0 0 0 0 0.075375 0.145069 0.145069 0.145069 0.145069
  spline S107 degree 3 poles (-45.9986, -80.5593) (-46.0272, -80.6953) (-46.0886, -80.9865) (-46.1598, -81.2756) (-46.1978, -81.4297) knots 0 0 0 0 0.041663 0.089295 0.089295 0.089295 0.089295
  line L93 (-46.1978, -81.4297) -> (-46.8254, -84)
  line L94 (-46.8254, -84) -> (-47.3574, -84)
  line L95 (-47.3574, -84) -> (-46.2606, -80)
  line L96 (-46.2606, -80) -> (-45.7503, -80)
  line L97 (-45.7503, -80) -> (-44.9072, -83.0477)
  spline S108 degree 3 poles (-44.9072, -83.0477) (-44.8784, -83.1504) (-44.8346, -83.3063) (-44.7952, -83.4633) (-44.7817, -83.5171) knots 0 0 0 0 0.031971 0.048582 0.048582 0.048582 0.048582
  spline S109 degree 3 poles (-44.7817, -83.5171) (-44.7621, -83.4319) (-44.7258, -83.2747) (-44.6837, -83.119) (-44.6644, -83.0477) knots 0 0 0 0 0.026224 0.048378 0.048378 0.048378 0.048378
  line L98 (-35.0327, -81.6262) -> (-35.0327, -80)
  line L99 (-35.0327, -80) -> (-34.5034, -80)
  line L100 (-34.5034, -80) -> (-34.5034, -84)
  line L101 (-34.5034, -84) -> (-36.0123, -84)
  spline S110 degree 3 poles (-36.0123, -84) (-36.1296, -83.9996) (-36.3332, -83.999) (-36.5351, -83.9729) (-36.6207, -83.9618) knots 0 0 0 0 0.035143 0.061018 0.061018 0.061018 0.061018
  spline S111 degree 3 poles (-36.6207, -83.9618) (-36.713, -83.9431) (-36.8879, -83.9076) (-37.0418, -83.8175) (-37.1146, -83.7749) knots 0 0 0 0 0.028003 0.053127 0.053127 0.053127 0.053127
  spline S112 degree 3 poles (-37.1146, -83.7749) (-37.1784, -83.723) (-37.3106, -83.6155) (-37.3927, -83.4661) (-37.4352, -83.3888) knots 0 0 0 0 0.024427 0.050607 0.050607 0.050607 0.050607
  spline S113 degree 3 poles (-37.4352, -83.3888) (-37.4706, -83.3031) (-37.5428, -83.1283) (-37.552, -82.9394) (-37.5566, -82.8431) knots 0 0 0 0 0.027603 0.056277 0.056277 0.056277 0.056277
  spline S114 degree 3 poles (-37.5566, -82.8431) (-37.544, -82.6806) (-37.5193, -82.361) (-37.3266, -82.1053) (-37.2319, -81.9795) knots 0 0 0 0 0.047795 0.093992 0.093992 0.093992 0.093992
  spline S115 degree 3 poles (-37.2319, -81.9795) (-37.0848, -81.8771) (-36.7358, -81.6342) (-36.3068, -81.6291) (-36.0587, -81.6262) knots 0 0 0 0 0.052712 0.125014 0.125014 0.125014 0.125014
  line L102 (-36.0587, -81.6262) -> (-35.0327, -81.6262)
  line L103 (-30, -142) -> (-110, -142)
  line L104 (-110, -142) -> (-110, -114)
  line L105 (-110, -114) -> (-30, -114)
  line L106 (-30, -114) -> (-30, -142)
  arc A0 (-48, -46.7946) -> (-48, -41.2054) centre (-45, -44) ccw
  line L107 (-48, -46.7946) -> (-48, -64)
  arc A1 (-51, -67) -> (-48, -64) centre (-51, -64) ccw
  line L108 (-51, -67) -> (-89, -67)
  arc A2 (-92, -64) -> (-89, -67) centre (-89, -64) ccw
  line L109 (-92, -64) -> (-92, -46.7946)
  arc A3 (-92, -41.2054) -> (-92, -46.7946) centre (-95, -44) ccw
  line L110 (-92, -41.2054) -> (-92, -30)
  arc A4 (-89, -27) -> (-92, -30) centre (-89, -30) ccw
  line L111 (-89, -27) -> (-51, -27)
  arc A5 (-48, -30) -> (-51, -27) centre (-51, -30) ccw
  line L112 (-48, -30) -> (-48, -41.2054)
  arc A6 (0, -6) -> (-6, 0) centre (-6, -6) ccw
  line L113 (-6, 0) -> (-134, 0)
  arc A7 (-134, 0) -> (-140, -6) centre (-134, -6) ccw
  line L114 (-140, -6) -> (-140, -174)
  arc A8 (-140, -174) -> (-134, -180) centre (-134, -174) ccw
  line L115 (-134, -180) -> (-6, -180)
  arc A9 (-6, -180) -> (0, -174) centre (-6, -174) ccw
  line L116 (0, -174) -> (0, -6)
  circle A10 centre (-97, -62) radius 1.25
  circle A11 centre (-43, -32) radius 1.25
  circle A12 centre (-97, -32) radius 1.25
  circle A13 centre (-43, -62) radius 1.25
  circle A14 centre (-132, -172) radius 3.4
  circle A15 centre (-8, -8) radius 3.4
  circle A16 centre (-132, -8) radius 3.4
  circle A17 centre (-8, -172) radius 3.4
  line L117 (-53.3332, -165.7995) -> (-53.3332, -162.5)
  line L118 (-53.3332, -162.5) -> (-52.4069, -162.5)
  line L119 (-52.4069, -162.5) -> (-52.4069, -169.5)
  line L120 (-52.4069, -169.5) -> (-53.3332, -169.5)
  line L121 (-53.3332, -169.5) -> (-53.3332, -166.6255)
  line L122 (-53.3332, -166.6255) -> (-56.9717, -166.6255)
  line L123 (-56.9717, -166.6255) -> (-56.9717, -169.5)
  line L124 (-56.9717, -169.5) -> (-57.898, -169.5)
  line L125 (-57.898, -169.5) -> (-57.898, -162.5)
  line L126 (-57.898, -162.5) -> (-56.9717, -162.5)
  line L127 (-56.9717, -162.5) -> (-56.9717, -165.7995)
  line L128 (-56.9717, -165.7995) -> (-53.3332, -165.7995)
  spline S116 degree 3 poles (-82.4792, -162.8581) (-82.2354, -163.032) (-81.747, -163.3803) (-81.449, -163.901) (-81.2998, -164.1617) knots 0 0 0 0 0.088694 0.177656 0.177656 0.177656 0.177656
  spline S117 degree 3 poles (-81.2998, -164.1617) (-81.1828, -164.4411) (-80.9486, -165.0006) (-80.9154, -165.6062) (-80.8987, -165.9093) knots 0 0 0 0 0.09016 0.180486 0.180486 0.180486 0.180486
  spline S118 degree 3 poles (-80.8987, -165.9093) (-80.9258, -166.4454) (-80.9764, -167.4486) (-81.562, -168.2602) (-81.8346, -168.6381) knots 0 0 0 0 0.157115 0.294003 0.294003 0.294003 0.294003
  spline S119 degree 3 poles (-81.8346, -168.6381) (-82.1749, -168.9257) (-82.8724, -169.5149) (-83.7839, -169.5872) (-84.2507, -169.6241) knots 0 0 0 0 0.13023 0.266885 0.266885 0.266885 0.266885
  spline S120 degree 3 poles (-84.2507, -169.6241) (-84.5634, -169.6063) (-85.1779, -169.5711) (-85.7281, -169.2961) (-85.9983, -169.161) knots 0 0 0 0 0.09288 0.182493 0.182493 0.182493 0.182493
  spline S121 degree 3 poles (-85.9983, -169.161) (-86.2427, -168.9907) (-86.734, -168.6482) (-87.034, -168.1299) (-87.1849, -167.8694) knots 0 0 0 0 0.088191 0.177305 0.177305 0.177305 0.177305
  spline S122 degree 3 poles (-87.1849, -167.8694) (-87.3039, -167.5785) (-87.5502, -166.9766) (-87.5785, -166.3264) (-87.5931, -165.9905) knots 0 0 0 0 0.093548 0.193567 0.193567 0.193567 0.193567
  spline S123 degree 3 poles (-87.5931, -165.9905) (-87.5776, -165.6496) (-87.5474, -164.9885) (-87.2887, -164.38) (-87.1634, -164.0853) knots 0 0 0 0 0.10144 0.196707 0.196707 0.196707 0.196707
  spline S124 degree 3 poles (-87.1634, -164.0853) (-87.007, -163.8231) (-86.6982, -163.3057) (-86.1944, -162.9756) (-85.9458, -162.8128) knots 0 0 0 0 0.090264 0.178186 0.178186 0.178186 0.178186
  spline S125 degree 3 poles (-85.9458, -162.8128) (-85.6774, -162.6867) (-85.1385, -162.4337) (-84.5442, -162.3984) (-84.2459, -162.3806) knots 0 0 0 0 0.088069 0.176826 0.176826 0.176826 0.176826
  spline S126 degree 3 poles (-84.2459, -162.3806) (-83.928, -162.3988) (-83.3053, -162.4344) (-82.7507, -162.7189) (-82.4792, -162.8581) knots 0 0 0 0 0.094347 0.184819 0.184819 0.184819 0.184819
  line L129 (-75.059, -165.6085) -> (-75.059, -162.5)
  line L130 (-75.059, -162.5) -> (-74.1327, -162.5)
  line L131 (-74.1327, -162.5) -> (-74.1327, -169.5)
  line L132 (-74.1327, -169.5) -> (-77.2364, -169.5)
  spline S127 degree 3 poles (-77.2364, -169.5) (-77.5129, -169.4979) (-77.9958, -169.4942) (-78.4606, -169.3661) (-78.6593, -169.3114) knots 0 0 0 0 0.082502 0.144074 0.144074 0.144074 0.144074
  spline S128 degree 3 poles (-78.6593, -169.3114) (-78.8143, -169.2351) (-79.1303, -169.0795) (-79.3339, -168.7918) (-79.4376, -168.6453) knots 0 0 0 0 0.050986 0.1039 0.1039 0.1039 0.1039
  spline S129 degree 3 poles (-79.4376, -168.6453) (-79.5225, -168.4811) (-79.6939, -168.15) (-79.7171, -167.7778) (-79.7288, -167.59) knots 0 0 0 0 0.054798 0.110545 0.110545 0.110545 0.110545
  spline S130 degree 3 poles (-79.7288, -167.59) (-79.7101, -167.3529) (-79.6732, -166.8863) (-79.3872, -166.5163) (-79.2466, -166.3342) knots 0 0 0 0 0.06969 0.137147 0.137147 0.137147 0.137147
  spline S131 degree 3 poles (-79.2466, -166.3342) (-79.0499, -166.1779) (-78.613, -165.8305) (-78.0605, -165.7365) (-77.7568, -165.6849) knots 0 0 0 0 0.074231 0.16486 0.16486 0.16486 0.16486
  spline S132 degree 3 poles (-77.7568, -165.6849) (-77.8672, -165.6303) (-78.0651, -165.5325) (-78.2387, -165.3965) (-78.3155, -165.3363) knots 0 0 0 0 0.036803 0.066003 0.066003 0.066003 0.066003
  spline S133 degree 3 poles (-78.3155, -165.3363) (-78.4516, -165.2003) (-78.7376, -164.9146) (-78.965, -164.5803) (-79.0842, -164.4052) knots 0 0 0 0 0.057592 0.120984 0.120984 0.120984 0.120984
  line L133 (-79.0842, -164.4052) -> (-80.3018, -162.5)
  line L134 (-80.3018, -162.5) -> (-79.1368, -162.5)
  line L135 (-79.1368, -162.5) -> (-78.2104, -163.9563)
  spline S134 degree 3 poles (-78.2104, -163.9563) (-78.0894, -164.1434) (-77.8767, -164.472) (-77.6427, -164.7857) (-77.5419, -164.9209) knots 0 0 0 0 0.066812 0.117382 0.117382 0.117382 0.117382
  spline S135 degree 3 poles (-77.5419, -164.9209) (-77.4629, -165.0196) (-77.3237, -165.1936) (-77.1477, -165.3299) (-77.0716, -165.3888) knots 0 0 0 0 0.037771 0.066551 0.066551 0.066551 0.066551
  spline S136 degree 3 poles (-77.0716, -165.3888) (-77.0032, -165.4297) (-76.87, -165.5093) (-76.7213, -165.5535) (-76.649, -165.575) knots 0 0 0 0 0.023822 0.04634 0.04634 0.04634 0.04634
  spline S137 degree 3 poles (-76.649, -165.575) (-76.5799, -165.5847) (-76.4089, -165.6086) (-76.2362, -165.6085) (-76.1334, -165.6085) knots 0 0 0 0 0.020922 0.051731 0.051731 0.051731 0.051731
  line L136 (-76.1334, -165.6085) -> (-75.059, -165.6085)
  line L137 (-68.5222, -165.3458) -> (-68.5222, -162.5)
  line L138 (-68.5222, -162.5) -> (-67.5958, -162.5)
  line L139 (-67.5958, -162.5) -> (-67.5958, -169.5)
  line L140 (-67.5958, -169.5) -> (-70.2364, -169.5)
  spline S138 degree 3 poles (-70.2364, -169.5) (-70.4416, -169.4994) (-70.798, -169.4983) (-71.1513, -169.4525) (-71.3012, -169.4332) knots 0 0 0 0 0.061499 0.106781 0.106781 0.106781 0.106781
  spline S139 degree 3 poles (-71.3012, -169.4332) (-71.4625, -169.4004) (-71.7687, -169.3383) (-72.038, -169.1806) (-72.1654, -169.1061) knots 0 0 0 0 0.049005 0.092972 0.092972 0.092972 0.092972
  spline S140 degree 3 poles (-72.1654, -169.1061) (-72.2771, -169.0153) (-72.5084, -168.8272) (-72.6521, -168.5657) (-72.7265, -168.4304) knots 0 0 0 0 0.042748 0.088562 0.088562 0.088562 0.088562